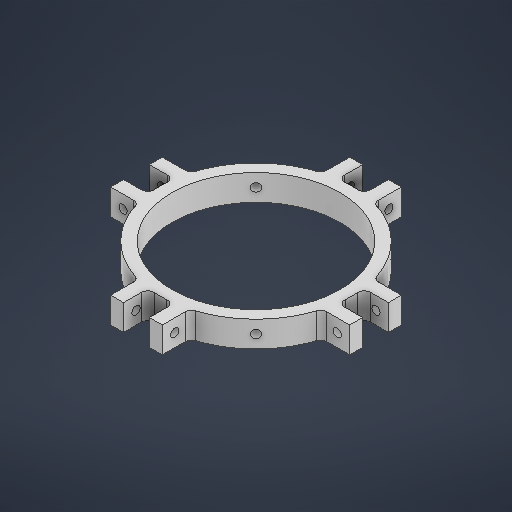
# Autodesk Inventor part: Upper leg ring_1
Saved by Autodesk Inventor 2027 (Build 310192060, 192F)
## iProperties
Created: 2026-06-30
Part Number: Upper leg ring_1
Material: PET Plastic
Document SubType Name: Modeling
Designer: troop
Density: 1.541 g/cm^3
Appearance: Default
Mass: 67.0549 g
Surface Area: 237.977 cm^2
Volume: 43.5139 cm^3
Author: troop
Autodesk Inventor part; units mm, degrees
ref_plane "YZ Plane" through (0, 0, 0) normal (1, 0, 0) x (0, 1, 0)
sketch "Sketch1" plane through (0, 0, 0) normal (0, 1, 0) x (-1, 0, 0)
  circle A0 centre (0, 0) radius 41.275
  circle A1 centre (0, 0) radius 46.99
  dimension "d0" = 82.55
  dimension "d1" = 93.98
  constraints: 2 centre point, 2 coincident
  measures "d0" diameter of A0
  measures "d1" diameter of A1
sketch "Sketch2" plane through (0, 0, 0) normal (0, 1, 0) x (-1, 0, 0)
  circle A0 centre (0, 0) radius 44.45 projected
  line L0 (-44.45, 0) -> (-44.45, -12.7)
  line L1 (-44.45, 0) -> (-44.45, 12.7)
  line L2 (-42.5971, -12.7) -> (-58.7825, -12.7)
  line L3 (-58.7825, -12.7) -> (-58.7825, -6.35)
  line L4 (-58.7825, -6.35) -> (-43.9941, -6.35)
  line L5 (-42.5971, 12.7) -> (-58.7825, 12.7)
  line L6 (-58.7825, 12.7) -> (-58.7825, 6.35)
  line L7 (-58.7825, 6.35) -> (-43.9941, 6.35)
  line L8 (12.7, -42.5971) -> (12.7, -58.7825)
  line L9 (0, -44.45) -> (12.7, -44.45)
  line L10 (6.35, -58.7825) -> (6.35, -43.9941)
  line L11 (12.7, -58.7825) -> (6.35, -58.7825)
  line L12 (-6.35, -58.7825) -> (-6.35, -43.9941)
  line L13 (0, -44.45) -> (-12.7, -44.45)
  line L14 (-12.7, -42.5971) -> (-12.7, -58.7825)
  line L15 (-12.7, -58.7825) -> (-6.35, -58.7825)
  line L16 (42.5971, 12.7) -> (58.7825, 12.7)
  line L17 (44.45, 0) -> (44.45, 12.7)
  line L18 (58.7825, 6.35) -> (43.9941, 6.35)
  line L19 (58.7825, 12.7) -> (58.7825, 6.35)
  line L20 (58.7825, -6.35) -> (43.9941, -6.35)
  line L21 (44.45, 0) -> (44.45, -12.7)
  line L22 (42.5971, -12.7) -> (58.7825, -12.7)
  line L23 (58.7825, -12.7) -> (58.7825, -6.35)
  line L24 (-12.7, 42.5971) -> (-12.7, 58.7825)
  line L25 (0, 44.45) -> (-12.7, 44.45)
  line L26 (-6.35, 58.7825) -> (-6.35, 43.9941)
  line L27 (-12.7, 58.7825) -> (-6.35, 58.7825)
  line L28 (6.35, 58.7825) -> (6.35, 43.9941)
  line L29 (0, 44.45) -> (12.7, 44.45)
  line L30 (12.7, 42.5971) -> (12.7, 58.7825)
  line L31 (12.7, 58.7825) -> (6.35, 58.7825)
  point P0 (-6.35, -44.45)
  point P1 (6.35, -44.45)
  point P2 (44.45, -6.35)
  point P3 (44.45, 6.35)
  point P4 (6.35, 44.45)
  point P5 (-6.35, 44.45)
  point P6 (-44.45, 6.35)
  point P7 (-44.45, -6.35)
  dimension "d4" = 12.7
  dimension "d5" = 12.7
  dimension "d6" = 16.1854
  dimension "d7" = 16.1854
  dimension "d8" = 6.35
  dimension "d9" = 6.35
  dimension "d10" = 14.7884
  dimension "d13" = 360
  constraints: 64 end point, 8 point on line, 5 point on circle, 3 perpendicular, 2 vertical, 1 horizontal, 1 parallel, 1 tangent, 77 other
  measures "d4" distance of L0.start L0.end
  measures "d5" distance of L0.start L1.end
  measures "d6" distance of L2.start L2.end
  measures "d7" distance of L5.start L5.end
  measures "d8" distance of L5.end L6.end
  measures "d9" distance of L2.end L3.end
  measures "d10" distance of L3.end L4.end
extrude "Extrusion2" add sketch "Sketch2" against normal blind 12.7
ref_plane "Work Plane1" through (-31.4309, 0, 31.4309) normal (-0.7071, 0, 0.7071) x (0, -1, 0)
ref_plane "Work Plane2" through (31.4309, 0, 31.4309) normal (0.7071, 0, 0.7071) x (0, 1, 0)
extrude "Extrusion10" add sketch "Sketch1" against normal blind 12.7
extrude "Extrusion11" cut sketch "Sketch1" against normal blind 12.7 contours A0
sketch "Sketch9" plane through (12.7, -12.7, 58.7825) normal (1, 0, 0) x (0, 0, -1)
  circle A0 centre (6.1087, 6.35) radius 1.9939
  line L0 (0, 12.7) -> (0, 0) projected
  line L1 (13.5412, 0) -> (0, 0) projected
  point P0 (58.7825, 12.7)
  dimension "d53" = 3.9878
  dimension "d54" = 6.1087
  dimension "d55" = 6.35
  constraints: 1 centre point
  measures "d53" diameter of A0
  measures "d54" distance from line of L0 A0.centre
  measures "d55" distance from line of L1 A0.centre
extrude "Extrusion12" cut sketch "Sketch9" against normal blind 50.8
sketch "Sketch10" plane through (58.7825, -12.7, 12.7) normal (0, 0, 1) x (1, 0, 0)
  circle A0 centre (-6.1087, 6.35) radius 1.9939
  line L0 (0, 12.7) -> (0, 0) projected
  line L1 (0, 0) -> (-13.5412, 0) projected
  point P0 (-58.7825, 12.7)
  dimension "d58" = 3.9878
  dimension "d59" = 6.1087
  dimension "d60" = 6.35
  constraints: 1 centre point
  measures "d58" diameter of A0
  measures "d59" distance from line of L0 A0.centre
  measures "d60" distance from line of L1 A0.centre
sketch "Sketch11" plane through (12.7, -12.7, -58.7825) normal (1, 0, 0) x (0, 0, -1)
  circle A0 centre (-6.1087, 6.35) radius 1.9939
  line L0 (0, 12.7) -> (0, 0) projected
  line L1 (0, 0) -> (-13.5412, 0) projected
  point P0 (-58.7825, 12.7)
  dimension "d61" = 3.9878
  dimension "d62" = 6.1087
  dimension "d63" = 6.35
  constraints: 1 centre point
  measures "d61" diameter of A0
  measures "d62" distance from line of L0 A0.centre
  measures "d63" distance from line of L1 A0.centre
sketch "Sketch12" plane through (-58.7825, -12.7, 12.7) normal (0, 0, 1) x (1, 0, 0)
  circle A0 centre (6.1087, 6.35) radius 1.9939
  line L0 (0, 12.7) -> (0, 0) projected
  line L1 (13.5412, 0) -> (0, 0) projected
  point P0 (58.7825, 12.7)
  dimension "d64" = 3.9878
  dimension "d65" = 6.1087
  dimension "d66" = 6.35
  constraints: 1 centre point
  measures "d64" diameter of A0
  measures "d65" distance from line of L0 A0.centre
  measures "d66" distance from line of L1 A0.centre
extrude "Extrusion13" cut sketch "Sketch12" against normal blind 50.8
extrude "Extrusion14" cut sketch "Sketch10" against normal blind 50.8
extrude "Extrusion15" cut sketch "Sketch11" against normal blind 50.8
fillet "Fillet1" radius 3.175 16 edges at (-45.2412, -6.35, 12.7) (-46.559, -6.35, 6.35) (-46.559, -6.35, -6.35) (-45.2412, -6.35, -12.7) (-12.7, -6.35, -45.2412) (-6.35, -6.35, -46.559) (12.7, -6.35, -45.2412) (6.35, -6.35, -46.559) (45.2412, -6.35, -12.7) (46.559, -6.35, 6.35) (46.559, -6.35, -6.35) (45.2412, -6.35, 12.7) (12.7, -6.35, 45.2412) (6.35, -6.35, 46.559) (-12.7, -6.35, 45.2412) (-6.35, -6.35, 46.559)
sketch "Sketch13" plane through (-31.4309, 0, 31.4309) normal (-0.7071, 0, 0.7071) x (0, -1, 0)
  circle A0 centre (6.35, 0) radius 1.9939
  line L0 (0, 21.0045) -> (0, -21.0045) projected
  line L1 (12.7, -21.0045) -> (12.7, 21.0045) projected
  point P0 (0, 0)
  point P1 (0, 0)
  point P2 (12.7, 0)
  dimension "d74" = 3.9878
  dimension "d75" = 0
  dimension "d76" = 6.35
  constraints: 2 midpoint, 1 centre point
  measures "d74" diameter of A0
  measures "d75" vertical distance of point (0, 0) A0.centre
  measures "d76" distance of point (12.7, 0) A0.centre
extrude "Extrusion16" cut sketch "Sketch13" along normal mid plane 254
sketch "Sketch14" plane through (31.4309, 0, 31.4309) normal (0.7071, 0, 0.7071) x (0, 1, 0)
  circle A0 centre (-6.35, 0) radius 1.9939
  line L0 (0, -21.0045) -> (0, 21.0045) projected
  line L1 (-12.7, 21.0045) -> (-12.7, -21.0045) projected
  point P0 (0, 0)
  point P1 (0, 0)
  point P2 (-12.7, 0)
  dimension "d79" = 3.9878
  dimension "d80" = 0
  dimension "d81" = 6.35
  constraints: 2 midpoint, 1 centre point
  measures "d79" diameter of A0
  measures "d80" vertical distance of point (0, 0) A0.centre
  measures "d81" distance of point (-12.7, 0) A0.centre
extrude "Extrusion17" cut sketch "Sketch14" along normal mid plane 254
body "Solid1"
